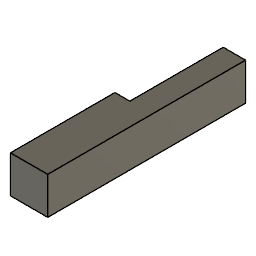
Right Fake Cross Beam (Autodesk Fusion 360 design; units mm, degrees)
Autodesk Fusion 360 part; units mm, degrees
sketch "Sketch1" plane through (0, 0, 0) normal (1, 0, 0) x (0, 1, 0)
  circle A0 centre (0, 0) radius 2.1971
  circle A1 centre (25.4, 0) radius 2.1971
  line L0 (10.16, 2.54) -> (15.24, 2.54)
  line L1 (15.24, 2.54) -> (15.24, -2.54)
  line L2 (15.24, -2.54) -> (10.16, -2.54)
  line L3 (10.16, -2.54) -> (10.16, 2.54)
  line L4 (-6.35, 4.7625) -> (31.75, 4.7625)
  line L5 (31.75, 4.7625) -> (31.75, -4.7625)
  line L6 (31.75, -4.7625) -> (-6.35, -4.7625)
  line L7 (-6.35, -4.7625) -> (-6.35, 4.7625)
  dimension "d1" = 25.4
  dimension "d2" = 4.3942
  dimension "d3" = 4.3942
  dimension "d4" = 5.08
  dimension "d5" = 5.08
  dimension "d6" = 2.54
  dimension "d7" = 10.16
  dimension "d8" = 9.525
  dimension "d9" = 38.1
  dimension "d10" = 4.7625
  dimension "d11" = 6.35
  constraint horizontal A0.centre A1.centre
  constraint horizontal L0
  constraint vertical L1
  constraint horizontal L2
  constraint vertical L3
  constraint coincident A0.centre origin
  constraint horizontal L4
  constraint vertical L5
  constraint horizontal L6
  constraint vertical L7
  measures "d1" distance of A0.centre A1.centre
  measures "d2" diameter of A0
  measures "d3" diameter of A1
  measures "d4" distance of L0.start L0.end
  measures "d5" distance of L0.start L2.end
  measures "d6" distance of A0.centre L0
  measures "d7" horizontal distance of A0.centre L2.end
  measures "d8" distance of L4.start L6.end
  measures "d9" distance of L4.start L4.end
  measures "d10" distance of A0.centre L4
  measures "d11" distance of A0.centre L7
extrude "Extrude1" add sketch "Sketch1" along normal blind 2.54 contours A0 | A1 | L0 L1 L2 L3 | L4 L5 L6 L7 makes body 1
sketch "Sketch2" plane through (2.54, 0, 0) normal (1, 0, 0) x (0, 1, 0)
  line L0 (-6.35, -4.7625) -> (31.75, -4.7625)
  line L1 (31.75, -4.7625) -> (31.75, 4.7625)
  line L2 (31.75, 4.7625) -> (-6.35, 4.7625)
  line L3 (-6.35, 4.7625) -> (-6.35, -4.7625)
  line L4 (31.75, 4.7625) -> (-6.35, 4.7625)
  line L5 (-6.35, 4.7625) -> (-6.35, -4.7625)
  line L6 (-6.35, -4.7625) -> (31.75, -4.7625)
  line L7 (31.75, -4.7625) -> (31.75, 4.7625)
  circle A0 centre (0, 0) radius 2.1971
  circle A1 centre (25.4, 0) radius 2.1971
  dimension "d14" = 4.3942
  dimension "d15" = 4.3942
  constraint horizontal L4
  constraint vertical L5
  constraint horizontal L6
  constraint vertical L7
  constraint coincident L0.start L3.end
  constraint coincident L1.end L2.start
  measures "d14" diameter of A0
  measures "d15" diameter of A1
extrude "Extrude2" add sketch "Sketch2" along normal blind 3.81 contours L0 L1 L2 L3 L4 L5 L6 L7 | A0 | A1 bodies 1
sketch "Sketch3" plane through (0, -6.35, 0) normal (0, -1, 0) x (1, 0, 0)
  line L0 (0, 4.7625) -> (0, -4.7625)
  line L1 (0, -4.7625) -> (6.35, -4.7625)
  line L2 (6.35, -4.7625) -> (6.35, 4.7625)
  line L3 (6.35, 4.7625) -> (0, 4.7625)
  line L4 (0, 4.7625) -> (6.35, 4.7625)
  line L5 (6.35, 4.7625) -> (6.35, -4.7625)
  line L6 (6.35, -4.7625) -> (0, -4.7625)
  line L7 (0, -4.7625) -> (0, 4.7625)
  constraint horizontal L4
  constraint vertical L5
  constraint horizontal L6
  constraint vertical L7
  constraint coincident L1.end L2.start
  constraint coincident L0.start L3.end
extrude "Extrude3" add sketch "Sketch3" along normal blind 127 bodies 1
sketch "Sketch4" plane through (6.35, 0, 0) normal (1, 0, 0) x (0, 1, 0)
  line L0 (31.75, -4.7625) -> (31.75, 4.7625)
  line L1 (31.75, 4.7625) -> (-133.35, 4.7625)
  line L2 (-133.35, 4.7625) -> (-133.35, -4.7625)
  line L3 (-133.35, -4.7625) -> (31.75, -4.7625)
  circle A0 centre (-22.225, -1.5875) radius 1.6
  circle A1 centre (-47.625, -1.5875) radius 1.6
  dimension "d20" = 3.2
  dimension "d21" = 3.2
  dimension "d24" = 6.35
  dimension "d25" = 22.225
  dimension "d48" = 25.4
  constraint horizontal A0.centre A1.centre
  measures "d20" diameter of A0
  measures "d21" diameter of A1
  measures "d24" distance of L1 A0.centre
  measures "d25" horizontal distance of origin A0.centre
  measures "d48" distance of A0.centre A1.centre
sketch "Sketch5" plane through (0, -133.35, 0) normal (0, -1, 0) x (1, 0, 0)
  line L0 (0, -4.7625) -> (6.35, -4.7625)
  line L1 (6.35, -4.7625) -> (6.35, 4.7625)
  line L2 (6.35, 4.7625) -> (0, 4.7625)
  line L3 (0, 4.7625) -> (0, -4.7625)
  line L4 (0, -4.7625) -> (6.35, -4.7625)
  line L5 (6.35, -4.7625) -> (6.35, 1.5875)
  line L6 (6.35, 1.5875) -> (0, 1.5875)
  line L7 (0, 1.5875) -> (0, -4.7625)
  dimension "d29" = 6.35
  constraint horizontal L4
  constraint vertical L5
  constraint horizontal L6
  constraint vertical L7
  constraint coincident L1 L5.end
  constraint coincident L0.start L3.end
  measures "d29" distance of L0.end L5.end
extrude "Extrude5" cut sketch "Sketch5" against normal blind 67.945 contours L1 L2 L3 L6 bodies 1
sketch "Sketch6" plane through (0, 0, 0) normal (-1, 0, 0) x (0, -1, 0)
  line L0 (65.405, 1.5875) -> (65.405, 4.7625)
  line L1 (65.405, 4.7625) -> (-31.75, 4.7625)
  line L2 (-31.75, 4.7625) -> (-31.75, -4.7625)
  line L3 (-31.75, -4.7625) -> (133.35, -4.7625)
  line L4 (133.35, -4.7625) -> (133.35, 1.5875)
  line L5 (133.35, 1.5875) -> (65.405, 1.5875)
  circle A0 centre (117.475, -1.5875) radius 2.1
  dimension "d32" = 4.2
  dimension "d33" = 15.875
  dimension "d34" = 3.175
  measures "d32" diameter of A0
  measures "d33" distance of L4 A0.centre
  measures "d34" distance of L3 A0.centre
extrude "Extrude6" cut sketch "Sketch6" against normal blind 6.35 contours A0 bodies 1
sketch "Sketch7" plane through (6.35, 0, 0) normal (1, 0, 0) x (0, 1, 0)
  circle A0 centre (-117.475, -1.5875) radius 2.1
  line L0 (-65.405, 4.7625) -> (-65.405, 1.5875)
  line L1 (-65.405, 1.5875) -> (-133.35, 1.5875)
  line L2 (-133.35, 1.5875) -> (-133.35, -4.7625)
  line L3 (-133.35, -4.7625) -> (31.75, -4.7625)
  line L4 (31.75, -4.7625) -> (31.75, 4.7625)
  line L5 (31.75, 4.7625) -> (-65.405, 4.7625)
  circle A1 centre (-117.475, -11.4427) radius 2.1
  circle A2 centre (-117.475, -11.4427) radius 3.175
  circle A3 centre (-106.045, -11.4427) radius 2.1
  circle A4 centre (-106.045, -11.4427) radius 3.175
  line L6 (-117.475, -8.2677) -> (-106.045, -8.2677)
  line L7 (-117.475, -14.6177) -> (-106.045, -14.6177)
  line L8 (-65.405, 4.7625) -> (-65.405, -4.7625)
  line L9 (-106.045, -14.6177) -> (-70.9402, -14.6177)
  line L10 (-70.9402, -14.6177) -> (-65.405, -6.5046)
  line L11 (-106.045, -8.2677) -> (-74.295, -8.2677)
  line L12 (-74.295, -8.2677) -> (-65.405, 4.7625)
  line L13 (-65.405, -6.5046) -> (-65.405, -4.7625)
  line L14 (-65.405, -6.5046) -> (-64.2164, -4.7625)
  line L15 (-120.65, -8.2677) -> (-102.87, -8.2677)
  line L16 (-102.87, -8.2677) -> (-102.87, -14.6177)
  line L17 (-102.87, -14.6177) -> (-120.65, -14.6177)
  line L18 (-120.65, -14.6177) -> (-120.65, -8.2677)
  dimension "d37" = 9.8552
  dimension "d38" = 6.35
  dimension "d43" = 4.2
  dimension "d44" = 6.35
  dimension "d45" = 11.43
  dimension "d49" = 31.75
  dimension "d50" = 6.35
  constraint equal A0 A1
  constraint vertical A0.centre A1.centre
  constraint concentric A1 A2
  constraint concentric A3 A4
  constraint horizontal A1.centre A3.centre
  constraint coincident A2 L6.start
  constraint coincident A4 L6.end
  constraint parallel L3 L6
  constraint coincident A2 L7.start
  constraint coincident A4 L7.end
  constraint coincident L3 L8.end
  constraint horizontal L7
  constraint tangent A2 L7
  constraint tangent A2 L6
  constraint vertical L8.end L0.start
  constraint tangent A4 L9
  constraint parallel L3 L9
  constraint coincident L8 L10.end
  constraint tangent A4 L11
  constraint parallel L3 L11
  constraint coincident L0.start L5.end
  constraint vertical L0.start L5.end
  constraint parallel L10 L12
  constraint coincident L3 L14.end
  constraint parallel L10 L14
  constraint horizontal L15
  constraint vertical L16
  constraint horizontal L17
  constraint vertical L18
  constraint coincident L9 L16.end
  constraint tangent A4 L16
  constraint tangent A2 L18
  constraint coincident L11 L15.end
  measures "d37" vertical distance of A0.centre A1.centre
  measures "d38" diameter of A2
  measures "d43" diameter of A3
  measures "d44" diameter of A4
  measures "d45" distance of A1.centre A3.centre
  measures "d49" horizontal distance of A3.centre L11.end
  measures "d50" distance of L10 L12
extrude "Extrude7" cut sketch "Sketch7" against normal blind 6.35 contours L0 L1 L8 L12 | L1 L3 L8 L12 | L1 L2 L3 L12 bodies 1
extrude "Extrude8" add sketch "Sketch7" against normal blind 3.81 separate body contours L0 L1 L8 L12 | L1 L3 L8 L12 | L3 L9 L10 L11 L12 L13 L16 | L3 L13 L14 | A4 L11 L15 L16 | A4 L9 L16 L17 | A4 | A2 A4 L6 L7 L15 L17 | A2 | A2 L15 L18 | A2 L17 L18 | A1 | A3 makes body 2
extrude "Extrude9" add sketch "Sketch7" against normal blind 6.35 contours A4 L11 L15 L16 | A4 L9 L16 L17 | A4 | A2 A4 L6 L7 L15 L17 | A2 | A2 L15 L18 | A2 L17 L18 | A1 | A3 bodies 2
sketch "Sketch8" plane through (0, 0, 4.7625) normal (0, 0, 1) x (-1, 0, 0)
  line L0 (0, 65.405) -> (-6.35, 65.405)
  line L1 (-6.35, 65.405) -> (-6.35, -31.75)
  line L2 (-6.35, -31.75) -> (0, -31.75)
  line L3 (0, -31.75) -> (0, 65.405)
  line L4 (0, -31.75) -> (-6.35, -31.75)
  line L5 (-6.35, -31.75) -> (-6.35, 65.405)
  line L6 (-6.35, 65.405) -> (0, 65.405)
  line L7 (0, 65.405) -> (0, -31.75)
  constraint horizontal L4
  constraint vertical L5
  constraint horizontal L6
  constraint vertical L7
  constraint coincident L0.end L1.start
  constraint coincident L2.end L3.start
extrude "Extrude10" add sketch "Sketch8" along normal blind 0.4318 bodies 1 2
sketch "Sketch9" plane through (0, 31.75, 0) normal (0, 1, 0) x (-1, 0, 0)
  line L0 (0, -4.7625) -> (0, 5.1943)
  line L1 (0, 5.1943) -> (-6.35, 5.1943)
  line L2 (-6.35, 5.1943) -> (-6.35, -4.7625)
  line L3 (-6.35, -4.7625) -> (0, -4.7625)
  line L4 (-6.35, -4.7625) -> (0, -4.7625)
  line L5 (0, -4.7625) -> (0, 5.1943)
  line L6 (0, 5.1943) -> (-6.35, 5.1943)
  line L7 (-6.35, 5.1943) -> (-6.35, -4.7625)
  constraint horizontal L4
  constraint vertical L5
  constraint horizontal L6
  constraint vertical L7
  constraint coincident L0.end L1.start
  constraint coincident L2.end L3.start
extrude "Extrude11" add sketch "Sketch9" along normal blind 12.7 bodies 1
sketch "Sketch10" plane through (0, 0, -4.7625) normal (0, 0, -1) x (1, 0, 0)
  line L0 (6.35, 64.2164) -> (2.54, 64.2164)
  line L1 (2.54, 64.2164) -> (2.54, 65.405)
  line L2 (2.54, 65.405) -> (0, 65.405)
  line L3 (0, 65.405) -> (0, -44.45)
  line L4 (0, -44.45) -> (6.35, -44.45)
  line L5 (6.35, -44.45) -> (6.35, 64.2164)
  line L6 (6.35, -44.45) -> (0, -44.45)
  line L7 (0, -44.45) -> (0, 6.35)
  line L8 (0, 6.35) -> (6.35, 6.35)
  line L9 (6.35, 6.35) -> (6.35, -44.45)
  dimension "d55" = 50.8
  constraint horizontal L6
  constraint vertical L7
  constraint horizontal L8
  constraint vertical L9
  constraint coincident L3 L7.end
  constraint coincident L4.end L5.start
  measures "d55" distance of L4.end L8.end
extrude "Extrude12" add sketch "Sketch10" along normal blind 6.35 contours L3 L4 L5 L6 L7 L8 L9 bodies 1
sketch "Sketch11" plane through (0, 0, 0) normal (-1, 0, 0) x (0, -1, 0)
  line L0 (65.405, -4.7625) -> (65.405, 5.1943)
  line L1 (65.405, 5.1943) -> (-44.45, 5.1943)
  line L2 (-44.45, 5.1943) -> (-44.45, -11.1125)
  line L3 (-44.45, -11.1125) -> (6.35, -11.1125)
  line L4 (6.35, -11.1125) -> (6.35, -4.7625)
  line L5 (6.35, -4.7625) -> (65.405, -4.7625)
  line L6 (-44.45, 5.1943) -> (-44.45, -4.9657)
  line L7 (0.4841, -4.9657) -> (6.35, 5.1943)
  line L8 (-44.45, -4.9657) -> (0.4841, -4.9657)
  dimension "d58" = 60
  dimension "d59" = 50.8
  dimension "d60" = 10.16
  constraint coincident L1.end L2.start
  constraint coincident L1 L7.end
  constraint horizontal L8
  constraint vertical L6
  measures "d58" angle of L1 L7
  measures "d59" distance of L1.end L7.end
  measures "d60" distance of L1.end L6.end
extrude "Extrude13" cut sketch "Sketch11" against normal blind 6.35 contours L1 L2 L6 L7 L8 bodies 1
fillet "Fillet1" radius 19.05 1 edges at (3.175, -6.35, -4.7625) on bodies 1
fillet "Fillet2" radius 6.35 1 edges at (3.175, -0.4841, -4.9657) on bodies 1
sketch "Sketch13" plane through (0, 44.45, 0) normal (0, 1, 0) x (-1, 0, 0)
  line L0 (0, -4.9657) -> (-6.35, -4.9657)
  line L1 (-6.35, -4.9657) -> (-6.35, -11.1125)
  line L2 (-6.35, -11.1125) -> (0, -11.1125)
  line L3 (0, -11.1125) -> (0, -4.9657)
  line L4 (-26.6046, 16.2746) -> (24.1954, 16.2746)
  line L5 (24.1954, 16.2746) -> (24.1954, -34.5254)
  line L6 (24.1954, -34.5254) -> (-26.6046, -34.5254)
  line L7 (-26.6046, -34.5254) -> (-26.6046, 16.2746)
  dimension "d73" = 50.8
  dimension "d74" = 50.8
  dimension "d75" = 35.8333
  dimension "d76" = 24.1954
  constraint horizontal L4
  constraint vertical L5
  constraint horizontal L6
  constraint vertical L7
  measures "d73" distance of L4.start L6.end
  measures "d74" distance of L5.end L6.end
  measures "d75" distance of L0.end L6.end
  measures "d76" distance of L3 L5
extrude "Extrude17" cut sketch "Sketch13" against normal blind 118.745 contours L0 L1 L2 L3 | L4 L5 L6 L7 bodies 1
extrude "Extrude18" cut 1 faces at (5.08, -74.295, -10.3844) along direction (0, -1, 0) blind 12.7 on bodies 1 bodies 1
extrude "Extrude14" [suppressed]
extrude "Extrude15" [suppressed]
sketch "Sketch12" plane through (6.35, 0, 0) normal (1, 0, 0) x (0, 1, 0)
  line L0 (44.45, -4.9657) -> (3.1821, -4.9657)
  arc A0 (-2.3172, -1.7907) -> (3.1821, -4.9657) centre (3.1821, 1.3843) ccw
  line L1 (-2.3172, -1.7907) -> (-6.35, 5.1943)
  line L2 (-6.35, 5.1943) -> (-65.405, 5.1943)
  line L3 (-65.405, 5.1943) -> (-65.405, 4.7625)
  line L4 (-65.405, 4.7625) -> (-74.295, -8.2677)
  line L5 (-74.295, -8.2677) -> (-120.65, -8.2677)
  line L6 (-120.65, -8.2677) -> (-120.65, -14.6177)
  line L7 (-120.65, -14.6177) -> (-70.9402, -14.6177)
  line L8 (-70.9402, -14.6177) -> (-64.2164, -4.7625)
  line L9 (-64.2164, -4.7625) -> (-20.549, -4.7625)
  arc A1 (-6.35, -11.1125) -> (-20.549, -4.7625) centre (-20.549, -23.8125) ccw
  line L10 (-6.35, -11.1125) -> (44.45, -11.1125)
  line L11 (44.45, -11.1125) -> (44.45, -4.9657)
  line L12 (-74.295, -8.2677) -> (-74.295, -14.6177)
  constraint coincident L4.end L5.start
  constraint coincident L7 L12.end
  constraint perpendicular L7 L12
extrude "Extrude16" [suppressed]
equation "d7 = 0.5 in - ( 0.2 / 2 ) * 1 in"
equation "d10 = ( 0.375 / 2 ) * 1 in"
equation "d11 = ( ( 1.5 - 1 ) / 2 ) * 1 in"
equation "d37 = 0.263 in + 0.125 in"
